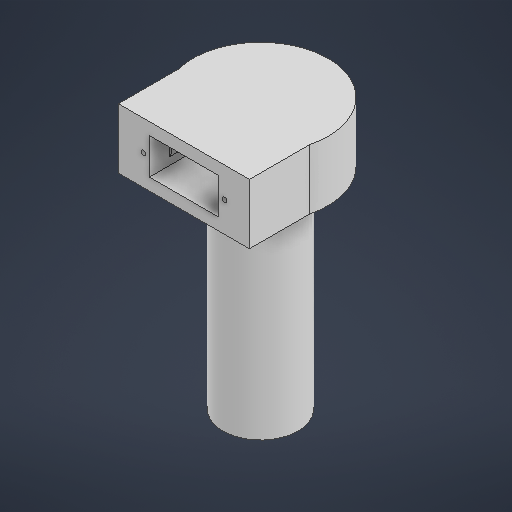
# Autodesk Inventor part: 360° Rotating arm v2
Saved by Autodesk Inventor 2026.1 (Build 301233020, 233B)
## iProperties
Created: 2026-09-21
Part Number: 360° Rotating arm v2
Material: Generico
Document SubType Name: Modeling
Designer: nuzzo
Mass: 68.1645 g
Surface Area: 139.809 cm^2
Volume: 68.1645 cm^3
Density: 1 g/cm^3
Appearance: Default
Author: nuzzo
Autodesk Inventor part; units mm, degrees
ref_plane "YZ Plane" through (0, 0, 0) normal (1, 0, 0) x (0, 1, 0)
ref_plane "XZ Plane" through (0, 0, 0) normal (0, 1, 0) x (-1, 0, 0)
ref_plane "XY Plane" through (0, 0, 0) normal (0, 0, 1) x (1, 0, 0)
sketch "Schizzo1" plane through (0, 0, 0) normal (0, 1, 0) x (-1, 0, 0)
  circle A0 centre (0, 0) radius 12.5
  dimension "d0" = 25
  constraints: 1 centre point, 1 coincident
  measures "d0" diameter of A0
extrude "Estrusione1" add sketch "Schizzo1" along normal blind 70
sketch "Schizzo2" plane through (0, 0, 0) normal (0, -1, 0) x (1, 0, 0)
  line L0 (-1.5, -2.5) -> (1.5, -2.5)
  line L1 (1.5, -2.5) -> (1.5, 2.5)
  line L2 (1.5, 2.5) -> (-1.5, 2.5)
  line L3 (-1.5, 2.5) -> (-1.5, -2.5)
  line L4 (-1.5, -2.5) -> (1.5, 2.5) construction
  line L5 (1.5, -2.5) -> (-1.5, 2.5) construction
  point P0 (0, 0)
  dimension "d3" = 3
  dimension "d4" = 5
  constraints: 12 end point, 2 midpoint, 2 parallel, 1 horizontal, 1 perpendicular
  measures "d3" distance of L2.end L1.end
  measures "d4" distance of L1.end L0.end
extrude "Estrusione2" cut sketch "Schizzo2" against normal blind 8
sketch "Schizzo4" plane through (0, 70, 0) normal (0, 1, 0) x (1, 0, 0)
  circle A0 centre (0, 0) radius 22.5
  line L0 (0, -5.5) -> (-21.8174, -5.5)
  line L1 (21.8174, -5.5) -> (0, -5.5)
  dimension "d10" = 45
  constraints: 4 end point, 2 point on circle, 1 centre point, 1 coincident, 1 collinear, 1 horizontal, 1 point on line
  measures "d10" diameter of A0
extrude "Estrusione4" add sketch "Schizzo4" along normal blind 20 contours A0 L1 L0 picked at (-0.0365, 13.0569)
sketch "Schizzo5" plane through (-21.8174, 70, 5.5) normal (0, 0, 1) x (1, 0, 0)
  line L0 (0, 20) -> (43.6348, 20)
  line L1 (43.6348, 20) -> (43.6348, 0)
  line L2 (43.6348, 0) -> (0, 0)
  line L3 (0, 0) -> (0, 20)
  point P0 (21.8174, -70)
  constraints: 8 end point, 2 parallel, 1 horizontal, 1 perpendicular
extrude "Estrusione5" add sketch "Schizzo5" along normal blind 20
sketch "Schizzo6" plane through (-21.8174, 70, 25.5) normal (0, 0, 1) x (1, 0, 0)
  line L0 (43.6348, 0) -> (43.6348, 20) projected
  line L1 (0, 20) -> (43.6348, 0)
  line L2 (0, 20) -> (0, 0) projected
  line L3 (0, 0) -> (43.6348, 20)
  line L4 (10.3174, 4) -> (33.3174, 4)
  line L5 (33.3174, 4) -> (33.3174, 16)
  line L6 (33.3174, 16) -> (10.3174, 16)
  line L7 (10.3174, 16) -> (10.3174, 4)
  line L8 (10.3174, 4) -> (33.3174, 16) construction
  line L9 (33.3174, 4) -> (10.3174, 16) construction
  point P0 (21.8174, -70)
  point P1 (21.8174, 10)
  dimension "d16" = 23
  dimension "d17" = 12
  constraints: 16 end point, 3 midpoint, 2 parallel, 1 horizontal, 1 perpendicular
  measures "d16" distance of L6.end L5.end
  measures "d17" distance of L5.end L4.end
extrude "Estrusione6" cut sketch "Schizzo6" against normal blind 17 contours L5 L4 L7 L3 L1 | L1 L3 L5 | L3 L1 L7 L6 L5 | L3 L7 L1
sketch "Schizzo7" plane through (-11.5, 74, 25.5) normal (1, 0, 0) x (0, 0, -1)
  line L0 (0, 0) -> (0, 12) projected
  line L1 (17, 0) -> (17, 12) projected
  line L2 (0, 0) -> (17, 12)
  line L3 (0, 12) -> (17, 0)
  circle A0 centre (8.5, 6) radius 6
  line L4 (17, 12) -> (8.5, 0)
  line L5 (17, 0) -> (8.5, 12)
  line L6 (8.75, 4.5) -> (16.75, 4.5)
  line L7 (16.75, 4.5) -> (16.75, 7.5)
  line L8 (16.75, 7.5) -> (8.75, 7.5)
  line L9 (8.75, 7.5) -> (8.75, 4.5)
  line L10 (8.75, 4.5) -> (16.75, 7.5) construction
  line L11 (16.75, 4.5) -> (8.75, 7.5) construction
  point P0 (25.5, -74)
  point P1 (12.75, 6)
  dimension "d20" = 8
  dimension "d21" = 3
  constraints: 20 end point, 4 midpoint, 2 parallel, 2 point on circle, 1 centre point, 1 horizontal, 1 perpendicular
  measures "d20" distance of L8.end L7.end
  measures "d21" distance of L7.end L6.end
extrude "Estrusione7" cut sketch "Schizzo7" against normal blind 17 contours L9 L8 L2 | L2 L8 L5 L4 L6 L3 L9 | L3 L6 L9 | L4 L5 L6 | L8 L4 L5 | L6 L5 L4 L8 A0 | A0 L8 L7 L6
fillet "Raccordo1" radius 6 1 edges at (12.5, 70, 0)
fillet "Raccordo2" radius 2 4 edges at (-21.8174, 81.5, 12.75) (-21.8174, 80, 8.75) (-21.8174, 78.5, 12.75) (-21.8174, 80, 16.75)
fillet "Raccordo3" radius 2 4 edges at (-11.5, 81.5, 12.75) (-11.5, 80, 16.75) (-11.5, 78.5, 12.75) (-11.5, 80, 8.75)
sketch "Schizzo8" plane through (-21.8174, 70, 25.5) normal (0, 0, 1) x (1, 0, 0)
  line L0 (0, 0) -> (0, 20) projected
  line L1 (10.3174, 4) -> (10.3174, 16) projected
  line L2 (10.3174, 4) -> (10.3174, 16)
  line L3 (43.6348, 0) -> (43.6348, 20) projected
  line L4 (33.3756, 4) -> (33.3756, 16)
  circle A0 centre (8.3174, 10) radius 1
  circle A1 centre (35.3756, 10) radius 1
  point P0 (21.8174, -70)
  dimension "d29" = 2
  dimension "d30" = 2
  constraints: 4 end point, 2 centre point, 1 collinear, 1 parallel
  measures "d29" diameter of A0
  measures "d30" diameter of A1
hole "Foro1" at (-13.5, 80, 25.5) at (13.5582, 80, 25.5) direction (0, 0, -1) diameter 1.567 depth 7 thread size "M2x0.4" class "6H" standard "ISO Metric profile"
